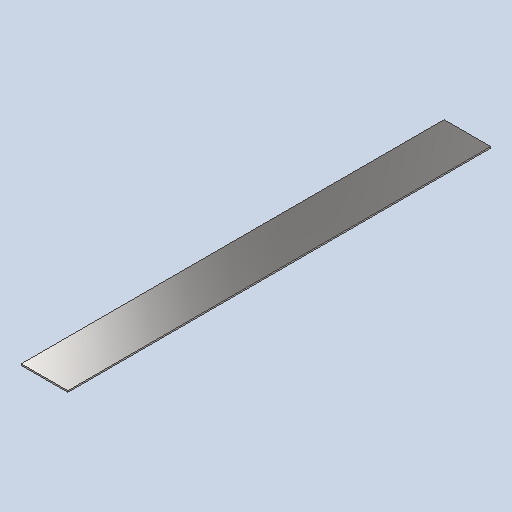
# Autodesk Inventor part: RDS-1208 Bunker Skirt Long
Saved by Autodesk Inventor 2026.2 (Build 302298000, 298)
## iProperties
Created: 2026-10-18
Part Number: RDS-1208 Bunker Skirt Long
Material: Stainless Steel, Austenitic
Description: Bunker skirt plate long, AISI 304 2 mm
Document SubType Name: Sheet Metal
Designer: admin
Stock Number: Юбка короба длинная (×2)
Density: 8 g/cm^3
Flat Pattern Width: 6.5 cm
Flat Pattern Length: 59 cm
Flat Pattern Area: 383.5 cm^2
Sheet Metal Rule: Default
Sheet Metal Width: 65,000 mm
Sheet Metal Length: 590,000 mm
Sheet Metal Area: 38350,000 mm^2
Appearance: Semi-Polished
Author: admin
Autodesk Inventor part; units mm, degrees
ref_plane "YZ Plane" through (0, 0, 0) normal (1, 0, 0) x (0, 1, 0)
ref_plane "XZ Plane" through (0, 0, 0) normal (0, 1, 0) x (-1, 0, 0)
ref_plane "XY Plane" through (0, 0, 0) normal (0, 0, 1) x (1, 0, 0)
sketch "Sketch1" plane through (0, 0, 0) normal (0, 1, 0) x (-1, 0, 0)
  line L0 (32.5, -295) -> (-32.5, -295)
  line L1 (-32.5, -295) -> (-32.5, 295)
  line L2 (-32.5, 295) -> (32.5, 295)
  line L3 (32.5, 295) -> (32.5, -295)
  dimension "d0" = 65
  dimension "d1" = 590
  measures "d0" distance of L0.start L0.end
  measures "d1" distance of L0.end L1.end
extrude "Plate1" add sketch "Sketch1" along normal blind 2
equation "\"d0\" = Skirt1208_Width"
equation "\"d1\" = Skirt1208_Length"
equation "\"d2\" = Thickness"
equation "\"BendRadius\" = Thickness"
equation "\"BendReliefWidth\" = Thickness"
equation "\"BendReliefDepth\" = 0.5 * Thickness"
equation "\"CornerReliefSize\" = 4 * Thickness"
equation "\"MinimumRemnant\" = 2 * Thickness"
equation "\"TransitionRadius\" = BendRadius"
equation "\"JacobiRadiusSize\" = BendRadius"
equation "\"GapSize\" = Thickness"
equation "\"Skirt1208_Width\" = 65"
equation "\"Skirt1208_Length\" = 590"
equation "\"Thickness\" = 2"
body "Solid1"
